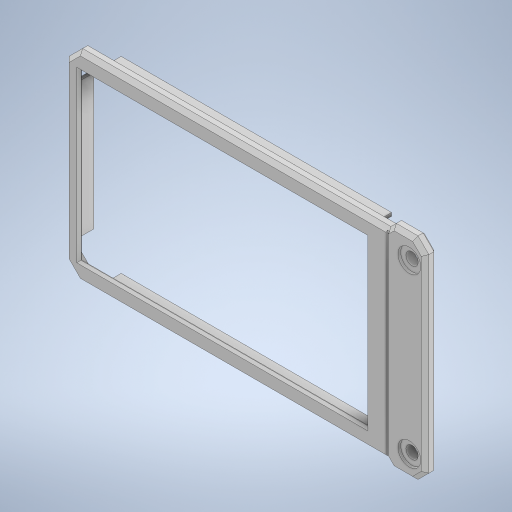
# Autodesk Inventor part: Cadre V2
Saved by Autodesk Inventor 2024 (Build 280153000, 153)
## iProperties
Created: 2026-10-31
Part Number: Cadre V2
Material: Générique
Document SubType Name: Modeling
Designer: berno
Density: 1 g/cm^3
Appearance: Par défaut
Author: berno
Autodesk Inventor part; units mm, degrees
sketch "Esq Cadre" plane through (0, 0, 0) normal (0, 0, 1) x (1, 0, 0)
  line L0 (-63, -32) -> (-63, 32)
  line L1 (-63, 32) -> (-58, 37)
  line L2 (-58, 37) -> (56, 37)
  line L3 (56, 37) -> (58, 39)
  line L4 (58, 39) -> (66, 39)
  line L5 (66, 39) -> (70, 35)
  line L6 (70, 35) -> (70, -35)
  line L7 (70, -35) -> (66, -39)
  line L8 (66, -39) -> (58, -39)
  line L9 (58, -39) -> (56, -37)
  line L10 (56, -37) -> (-58, -37)
  line L11 (-58, -37) -> (-63, -32)
  constraints: 24 end point
extrude "Cadre" add sketch "Esq Cadre" along normal blind 4
sketch "Esq Logement vitre" plane through (0, 0, 0) normal (0, 0, 1) x (1, 0, 0)
  line L0 (-61.5, -30.5) -> (-61.5, 30.5)
  line L1 (-61.5, 30.5) -> (-56.5, 35.5)
  line L2 (-56.5, 35.5) -> (56.5, 35.5)
  line L3 (56.5, 35.5) -> (61.5, 30.5)
  line L4 (61.5, 30.5) -> (61.5, -30.5)
  line L5 (61.5, -30.5) -> (56.5, -35.5)
  line L6 (56.5, -35.5) -> (-56.5, -35.5)
  line L7 (-56.5, -35.5) -> (-61.5, -30.5)
  constraints: 16 end point
extrude "Logement vitre" cut sketch "Esq Logement vitre" along normal blind 3
ref_plane "Plan de construction1" through (0, 0, 4) normal (0, 0, 1) x (1, 0, 0)
sketch "Esq Fenetre ecran" plane through (0, 0, 4) normal (0, 0, 1) x (1, 0, 0)
  line L0 (-58, -30.5) -> (48, -30.5)
  line L1 (48, -30.5) -> (48, 30.5)
  line L2 (48, 30.5) -> (-58, 30.5)
  line L3 (-58, 30.5) -> (-58, -30.5)
  constraints: 8 end point, 2 parallel, 1 horizontal, 1 perpendicular
extrude "Fenetre ecran" cut sketch "Esq Fenetre ecran" against normal blind 1.5
chamfer "Chanfrein avant" distance 1.4 angle 45 12 edges at (-60.5, 34.5, 4) (-1, 37, 4) (57, 38, 4) (62, 39, 4) (68, 37, 4) (70, 0, 4) (68, -37, 4) (62, -39, 4) (57, -38, 4) (-1, -37, 4) (-60.5, -34.5, 4) (-63, 0, 4)
chamfer "Chanfrein fenetre" distance 0.8 angle 45 4 edges at (48, 0, 4) (-5, -30.5, 4) (-58, 0, 4) (-5, 30.5, 4)
chamfer "Chanfrein logement" distance 1.4 angle 45 8 edges at (-59, 33, 3) (0, 35.5, 3) (59, 33, 3) (61.5, 0, 3) (59, -33, 3) (0, -35.5, 3) (-59, -33, 3) (-61.5, 0, 3)
ref_plane "Plan de construction2" through (0, 0, 4) normal (0, 0, 1) x (1, 0, 0)
sketch "Esq Rainure menton" plane through (0, 0, 4) normal (0, 0, 1) x (1, 0, 0)
  line L0 (55.6, -41) -> (56.4, -41)
  line L1 (56.4, -41) -> (56.4, 41)
  line L2 (56.4, 41) -> (55.6, 41)
  line L3 (55.6, 41) -> (55.6, -41)
  constraints: 8 end point, 2 parallel, 1 horizontal, 1 perpendicular
extrude "Rainure menton" cut sketch "Esq Rainure menton" against normal blind 0.5
ref_plane "Plan de construction3" through (0, 0, 4) normal (0, 0, 1) x (1, 0, 0)
sketch "Esq Trous vis M4" plane through (0, 0, 4) normal (0, 0, 1) x (1, 0, 0)
  circle A0 centre (64.2, 31) radius 2.25
  circle A1 centre (64.2, -31) radius 2.25
  constraints: 2 centre point
extrude "Trous vis M4" cut sketch "Esq Trous vis M4" against normal blind 5
ref_plane "Plan de construction4" through (0, 0, 4) normal (0, 0, 1) x (1, 0, 0)
sketch "Esq Lamages vis" plane through (0, 0, 4) normal (0, 0, 1) x (1, 0, 0)
  circle A0 centre (64.2, 31) radius 4.2
  circle A1 centre (64.2, -31) radius 4.2
  constraints: 2 centre point
extrude "Lamages vis" cut sketch "Esq Lamages vis" against normal blind 1
sketch "Esq Languette" plane through (0, 0, 0) normal (0, 0, 1) x (1, 0, 0)
  line L0 (-50, 34.15) -> (50, 34.15)
  line L1 (50, 34.15) -> (50, 35.35)
  line L2 (50, 35.35) -> (-50, 35.35)
  line L3 (-50, 35.35) -> (-50, 34.15)
  line L4 (-50, -35.35) -> (50, -35.35)
  line L5 (50, -35.35) -> (50, -34.15)
  line L6 (50, -34.15) -> (-50, -34.15)
  line L7 (-50, -34.15) -> (-50, -35.35)
  line L8 (-61.35, -25) -> (-60.15, -25)
  line L9 (-60.15, -25) -> (-60.15, 25)
  line L10 (-60.15, 25) -> (-61.35, 25)
  line L11 (-61.35, 25) -> (-61.35, -25)
  constraints: 24 end point, 6 parallel, 3 horizontal, 3 perpendicular
extrude "Languette" add sketch "Esq Languette" against normal blind 4
sketch "Esq Liaison languette" plane through (0, 0, 0) normal (0, 0, 1) x (1, 0, 0)
  line L0 (-50, 34.15) -> (50, 34.15)
  line L1 (50, 34.15) -> (50, 36)
  line L2 (50, 36) -> (-50, 36)
  line L3 (-50, 36) -> (-50, 34.15)
  line L4 (-50, -36) -> (50, -36)
  line L5 (50, -36) -> (50, -34.15)
  line L6 (50, -34.15) -> (-50, -34.15)
  line L7 (-50, -34.15) -> (-50, -36)
  line L8 (-62, -25) -> (-60.15, -25)
  line L9 (-60.15, -25) -> (-60.15, 25)
  line L10 (-60.15, 25) -> (-62, 25)
  line L11 (-62, 25) -> (-62, -25)
  constraints: 24 end point, 6 parallel, 3 horizontal, 3 perpendicular
extrude "Liaison languette" add sketch "Esq Liaison languette" along normal blind 1.6
chamfer "Chanfrein languette" distance 0.35 angle 45 12 edges at (0, 34.15, -4) (-50, 34.75, -4) (0, 35.35, -4) (50, 34.75, -4) (-60.75, -25, -4) (-61.35, 0, -4) (-60.75, 25, -4) (-60.15, 0, -4) (0, -35.35, -4) (-50, -34.75, -4) (0, -34.15, -4) (50, -34.75, -4)
ref_plane "Plan de construction5" through (0, 14.5, 0) normal (0, 1, 0) x (-1, 0, 0)
sketch "Esq Patte haut Y+" plane through (0, 14.5, 0) normal (0, 1, 0) x (-1, 0, 0)
  line L0 (61, -2.5) -> (62.25, -2.5)
  line L1 (62.25, -2.5) -> (62.25, -1.9)
  line L2 (62.25, -1.9) -> (61.85, -1.5)
  line L3 (61.85, -1.5) -> (61, -1.5)
  line L4 (61, -1.5) -> (61, -2.5)
  constraints: 10 end point
extrude "Patte haut Y+" add sketch "Esq Patte haut Y+" along normal mid plane 15
ref_plane "Plan de construction6" through (0, -14.5, 0) normal (0, 1, 0) x (-1, 0, 0)
sketch "Esq Patte haut Y-" plane through (0, -14.5, 0) normal (0, 1, 0) x (-1, 0, 0)
  line L0 (61, -2.5) -> (62.25, -2.5)
  line L1 (62.25, -2.5) -> (62.25, -1.9)
  line L2 (62.25, -1.9) -> (61.85, -1.5)
  line L3 (61.85, -1.5) -> (61, -1.5)
  line L4 (61, -1.5) -> (61, -2.5)
  constraints: 10 end point
extrude "Patte haut Y-" add sketch "Esq Patte haut Y-" along normal mid plane 15
sketch "Esq Ligne d'ombre" plane through (0, 0, 0) normal (0, 0, 1) x (1, 0, 0)
  line L0 (-75, -45) -> (75, -45)
  line L1 (75, -45) -> (75, 45)
  line L2 (75, 45) -> (-75, 45)
  line L3 (-75, 45) -> (-75, -45)
  line L4 (-62.3, -31.71) -> (-62.3, 31.71)
  line L5 (-62.3, 31.71) -> (-57.71, 36.3)
  line L6 (-57.71, 36.3) -> (56.29, 36.3)
  line L7 (56.29, 36.3) -> (58.29, 38.3)
  line L8 (58.29, 38.3) -> (65.71, 38.3)
  line L9 (65.71, 38.3) -> (69.3, 34.71)
  line L10 (69.3, 34.71) -> (69.3, -34.71)
  line L11 (69.3, -34.71) -> (65.71, -38.3)
  line L12 (65.71, -38.3) -> (58.29, -38.3)
  line L13 (58.29, -38.3) -> (56.29, -36.3)
  line L14 (56.29, -36.3) -> (-57.71, -36.3)
  line L15 (-57.71, -36.3) -> (-62.3, -31.71)
  constraints: 32 end point, 2 parallel, 1 horizontal, 1 perpendicular
extrude "Ligne d'ombre" cut sketch "Esq Ligne d'ombre" along normal blind 0.7
